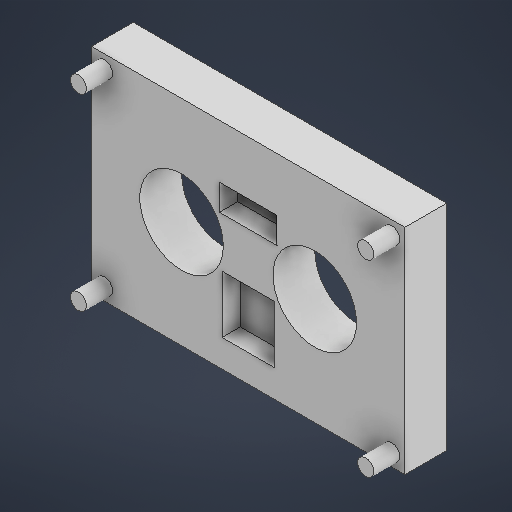
# Autodesk Inventor part: US_sensor_mount
Saved by Autodesk Inventor 2026.3 (Build 303398000, 398)
## iProperties
Created: 2026-09-23
Part Number: US_sensor_mount
Material: Generic
Document SubType Name: Modeling
Designer: grady
Density: 1 g/cm^3
Appearance: Default
Author: grady
Autodesk Inventor part; units mm, degrees
ref_plane "YZ Plane" through (0, 0, 0) normal (1, 0, 0) x (0, 1, 0)
ref_plane "XZ Plane" through (0, 0, 0) normal (0, 1, 0) x (-1, 0, 0)
ref_plane "XY Plane" through (0, 0, 0) normal (0, 0, 1) x (1, 0, 0)
sketch "Sketch1" plane through (0, 0, 0) normal (0, 0, 1) x (1, 0, 0)
  line L0 (0, 0) -> (60, 0)
  line L1 (60, 0) -> (60, 41)
  line L2 (60, 41) -> (0, 41)
  line L3 (0, 41) -> (0, 0)
  dimension "d0" = 60
  dimension "d1" = 41
  constraints: 8 end point, 2 parallel, 1 horizontal, 1 perpendicular
  measures "d0" distance of L2.end L1.end
  measures "d1" distance of L1.end L0.end
extrude "Extrusion1" add sketch "Sketch1" along normal blind 8
sketch "Sketch2" plane through (0, 0, 8) normal (0, 0, 1) x (1, 0, 0)
  line L0 (60, 20.5) -> (60, 10.25)
  line L1 (52.75, 30.75) -> (7.25, 30.75)
  line L2 (7.25, 30.75) -> (7.25, 10.25)
  line L3 (0, 41) -> (0, 0) projected
  line L4 (7.25, 10.25) -> (52.75, 10.25)
  line L5 (52.75, 10.25) -> (52.75, 30.75)
  circle A0 centre (17.25, 20.5) radius 8
  circle A1 centre (42.75, 20.5) radius 8
  dimension "d4" = 10.25
  dimension "d7" = 45.5
  dimension "d10" = 16
  dimension "d11" = 16
  constraints: 10 end point, 2 centre point, 2 perpendicular, 1 parallel
  measures "d4" distance of L0.start L0.end
  measures "d7" distance of L1.start L1.end
  measures "d10" diameter of A0
  measures "d11" diameter of A1
extrude "Extrusion2" cut sketch "Sketch2" against normal blind 10 contours A0 | A1
sketch "Sketch3" plane through (0, 0, 8) normal (0, 0, 1) x (1, 0, 0)
  line L0 (60, 0) -> (60, 41) projected
  line L1 (60, 10.25) -> (85, 10.25) construction
  line L2 (25, 16.25) -> (35, 16.25)
  line L3 (35, 16.25) -> (35, 5.25)
  line L4 (35, 5.25) -> (25, 5.25)
  line L5 (30, 30.75) -> (35.5, 30.75)
  line L6 (30, 30.75) -> (24.5, 30.75)
  line L7 (35.5, 30.75) -> (35.5, 25.75)
  line L8 (35.5, 25.75) -> (24.5, 25.75)
  line L9 (24.5, 25.75) -> (24.5, 30.75)
  line L10 (25, 16.25) -> (25, 5.25)
  dimension "d19" = 11
  dimension "d21" = 5.5
  dimension "d22" = 5.5
  dimension "d23" = 5
  dimension "d24" = 11
  constraints: 20 end point, 3 perpendicular, 2 horizontal, 2 vertical, 1 point on line
  measures "d19" distance of L2.end L3.end
  measures "d21" distance of L5.start L5.end
  measures "d22" distance of L5.start L6.end
  measures "d23" distance of L5.end L7.end
  measures "d24" distance of L7.end L8.end
extrude "Extrusion3" cut sketch "Sketch3" against normal blind 3.5
sketch "Sketch4" plane through (0, 0, 8) normal (0, 0, 1) x (1, 0, 0)
  line L0 (60, 0) -> (60, 41) projected
  circle A0 centre (2.5, 38.5) radius 1.55
  circle A1 centre (57.5, 38.5) radius 1.55
  circle A2 centre (57.5, 2.5) radius 1.55
  circle A3 centre (2.5, 2.5) radius 1.55
  point P0 (0, 0)
  point P1 (0, 41)
  dimension "d34" = 3.1
  dimension "d35" = 3.1
  dimension "d36" = 3.1
  dimension "d37" = 3.1
  constraints: 4 centre point, 4 coincident
  measures "d34" diameter of A0
  measures "d35" diameter of A1
  measures "d36" diameter of A2
  measures "d37" diameter of A3
extrude "Extrusion4" add sketch "Sketch4" along normal blind 5
body "Solid1"
